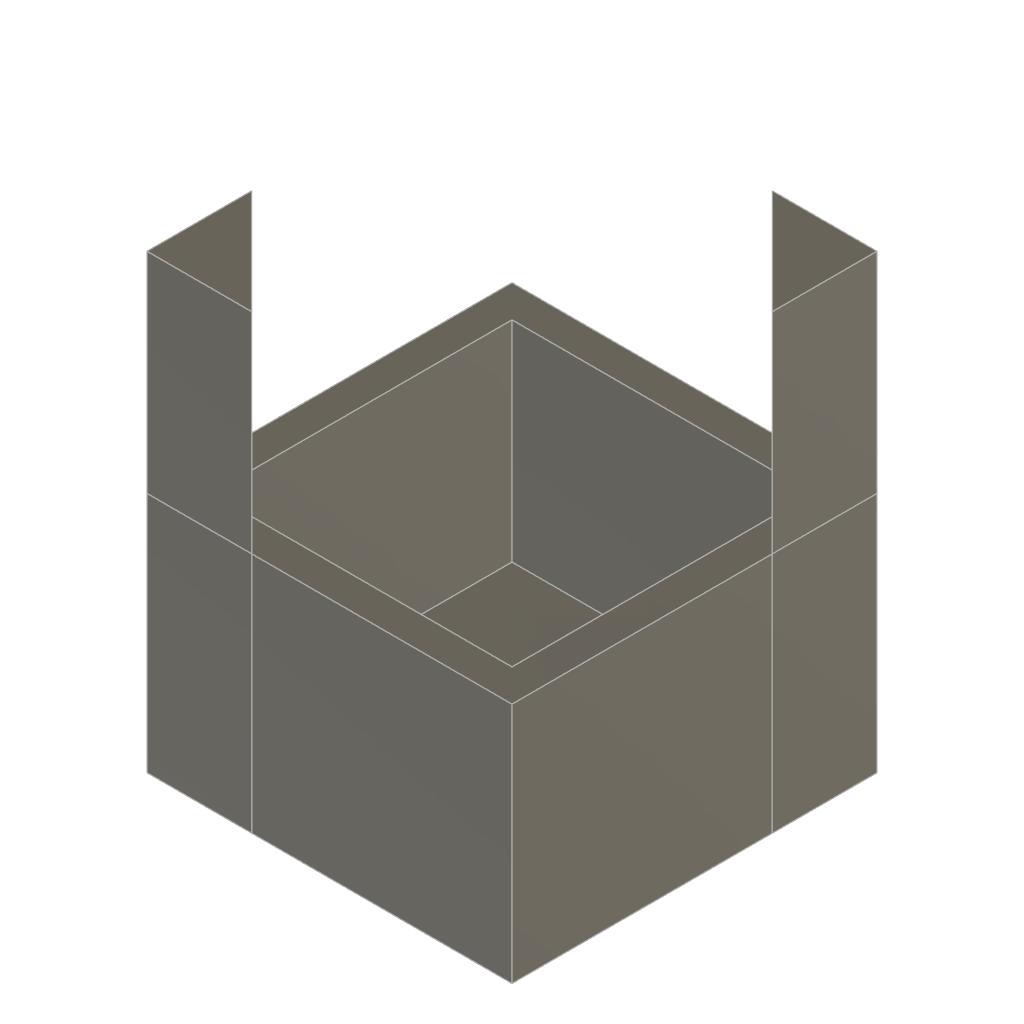
Base (Autodesk Fusion 360 design; units mm, degrees)
Autodesk Fusion 360 part; units mm, degrees
sketch "Base" plane through (0, 0, 0) normal (0, 0, 1) x (1, 0, 0)
  line L0 (0, 0) -> (22.6274, 22.6274) construction
  circle A0 centre (11.3137, 11.3137) radius 10 construction
  line L1 (0, 0) -> (22.6274, 0)
  line L2 (22.6274, 0) -> (22.6274, 22.6274)
  line L3 (22.6274, 22.6274) -> (0, 22.6274)
  line L4 (0, 22.6274) -> (0, 0)
  dimension "d9" = 32
  dimension "d11" = 20
  constraint coincident L0.start L1.start
  constraint midpoint L0 A0.centre
  constraint horizontal L1
  constraint vertical L2
  constraint horizontal L3
  constraint vertical L4
  measures "d9" distance of L0.start L0.end
  measures "d11" diameter of A0
extrude "Extrude2" add sketch "Base" along normal blind 15 makes body 1
shell "Shell2" thickness 2 removed faces 1 at (7.5425, 7.5425, 15) on bodies 1
sketch "Columns" plane through (0, 0, 0) normal (0, 0, 1) x (1, 0, 0)
  line L0 (3.25, 3.25) -> (6.5, 0)
  line L1 (6.5, 0) -> (0, 6.5)
  line L2 (0, 6.5) -> (0, 0)
  line L3 (0, 0) -> (6.5, 0)
  line L4 (0, 22.6274) -> (22.6274, 0) construction
  line L5 (22.6274, 16.1274) -> (16.1274, 22.6274)
  line L6 (16.1274, 22.6274) -> (22.6274, 22.6274)
  line L7 (22.6274, 22.6274) -> (22.6274, 16.1274)
  point P0 (0, 22.6274)
  point P1 (22.6274, 0)
  constraint parallel L0 L1
  constraint coincident L2.end L3.start
  constraint vertical L2
  constraint perpendicular L2 L3
  constraint coincident P0 L4.start
  constraint coincident P1 L4.end
  constraint symmetric L0.end L4 L5.start
  constraint symmetric L1.end L4 L5.end
  constraint symmetric L2.end L4 L6.end
  constraint midpoint L0.start L1
extrude "Extrude3" add sketch "Columns" along normal blind 28 separate body contours L0 L1 L2 L3 makes body 2
extrude "Extrude4" add sketch "Columns" along normal blind 28 separate body contours L5 L6 L7 makes body 3
ref_plane "WorkPlane2" through (0, 0, 25) normal (0, 0, 1) x (1, 0, 0)
sketch "FlipDotSpacing" plane through (0, 0, 25) normal (0, 0, 1) x (1, 0, 0)
  circle A0 centre (11.3137, 11.3137) radius 10 construction
  line L0 (0, 22.6274) -> (22.6274, 0)
  circle A1 through (21.3137, 11.3137, 0) (6.3137, 11.3137, 8.6603) (6.3137, 11.3137, -8.6603) construction
  circle A2 through (11.3137, 21.3137, 0) (11.3137, 6.3137, 8.6603) (11.3137, 6.3137, -8.6603) construction
  dimension "d25" = 20
  dimension "d27" = 20
  dimension "d28" = 20
  constraint midpoint A0.centre L0
  measures "d25" diameter of A0
sketch "Mounting Hole 1" plane through (3.25, 3.25, 0) normal (0.707107, 0.707107, 0) x (-0.707107, 0.707107, 0)
  line L0 (-4.5962, 0) -> (4.5962, 0)
  line L1 (4.5962, 0) -> (4.5962, 28)
  line L2 (4.5962, 28) -> (-4.5962, 28)
  line L3 (-4.5962, 28) -> (-4.5962, 0)
  circle A0 centre (0, 25) radius 1.25
  dimension "d30" = 2.5
  measures "d30" diameter of A0
extrude "Extrude5" cut sketch "Mounting Hole 1" against normal blind 2 contours A0 bodies 2
sketch "Mounting Hole 2" plane through (19.3774, 19.3774, 0) normal (-0.707107, -0.707107, 0) x (0.707107, -0.707107, 0)
  line L0 (-4.5962, 0) -> (4.5962, 0)
  line L1 (4.5962, 0) -> (4.5962, 28)
  line L2 (4.5962, 28) -> (-4.5962, 28)
  line L3 (-4.5962, 28) -> (-4.5962, 0)
  circle A0 centre (0, 25) radius 1.25
  dimension "d33" = 2.5
  measures "d33" diameter of A0
extrude "Extrude6" cut sketch "Mounting Hole 2" against normal blind 2 contours A0 bodies 3
